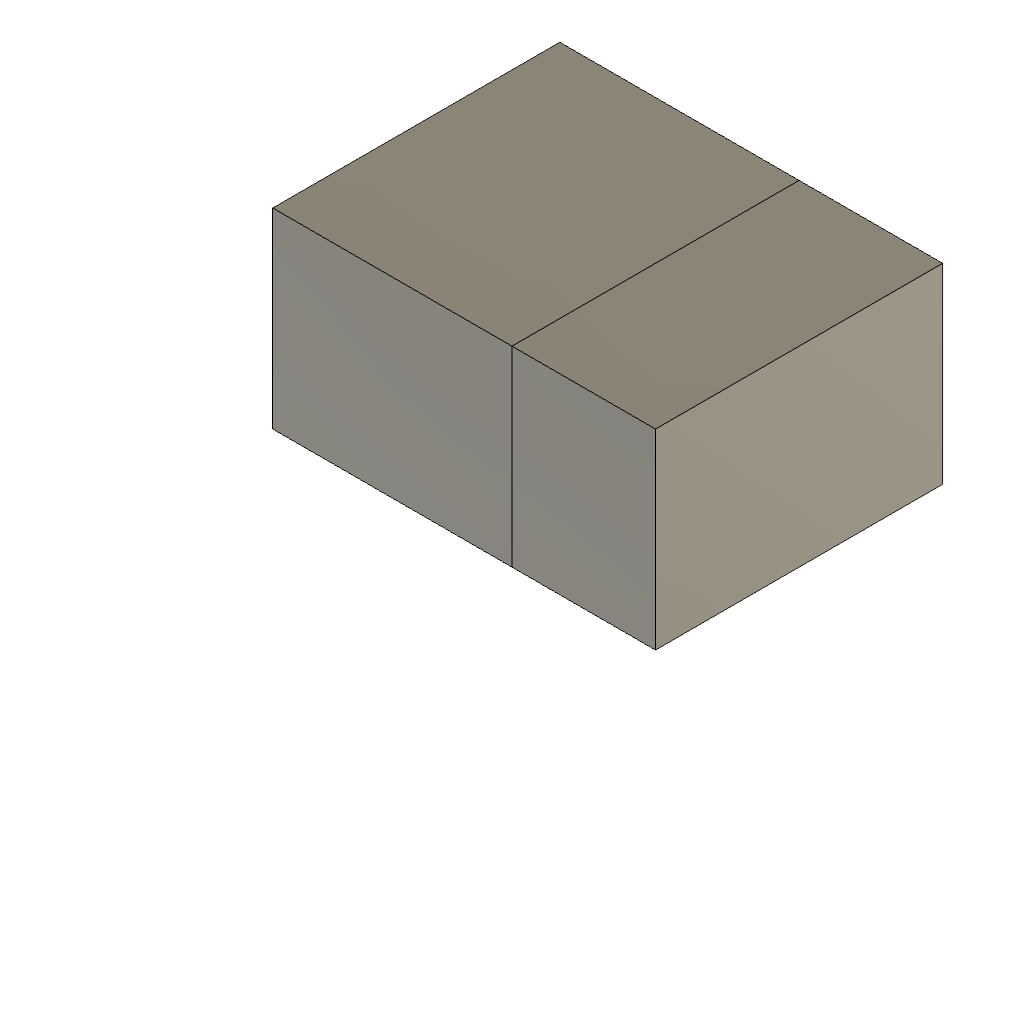
vendor_SplitYZ (Autodesk Fusion 360 design; units mm, degrees)
Autodesk Fusion 360 part; units mm, degrees
sketch "Base sketch" plane through (0, 0, 0) normal (0, 0, 1) x (1, 0, 0)
  line L0 (0, 0) -> (40, 0)
  line L1 (40, 0) -> (40, 30)
  line L2 (40, 30) -> (0, 30)
  line L3 (0, 30) -> (0, 0)
extrude "Base extrude" add sketch "Base sketch" along normal blind 20 makes body 1
ref_plane "WorkPlane1" through (25, 0, 0) normal (1, 0, 0) x (0, 1, 0)
split "Body split" by plane through (25, 0, 0) normal (1, 0, 0) bodies 1 makes body 2 at (40, 10, 6.6667)
equation "height = 20.0 mm"
